f3d-11a1882211a4 (Autodesk Fusion 360 design; units mm, degrees)
Autodesk Fusion 360 part; units mm, degrees
(part 1 of 3)
sketch "Sketch1" plane through (0, 0, 0) normal (0, 1, 0) x (1, 0, 0)
  line L0 (0, 0) -> (1000, 0) construction
  line L1 (1000, 0) -> (1000, -300) construction
  line L2 (1000, -300) -> (0, -300) construction
  line L3 (0, -300) -> (0, 0) construction
  line L4 (150, -300) -> (850, -300)
  arc A0 (850, -300) -> (850, 0) centre (850, -150) ccw
  line L5 (850, 0) -> (150, 0)
  arc A1 (150, 0) -> (150, -300) centre (150, -150) ccw
  line L6 (0, -150) -> (1000, -150) construction
  arc A2 (850, -270) -> (850, -30) centre (850, -150) ccw
  line L7 (850, -30) -> (150, -30)
  arc A3 (150, -30) -> (150, -270) centre (150, -150) ccw
  line L8 (150, -270) -> (850, -270)
  dimension "d1" = 300
  dimension "d2" = 1000
  dimension "d3" = -30
  constraint horizontal L0
  constraint vertical L1
  constraint horizontal L2
  constraint vertical L3
  constraint coincident L0.start L3.end
  constraint tangent L4 A0
  constraint tangent A0 L5
  constraint parallel L4 L5
  constraint tangent L5 A1
  constraint tangent L4 A1
  constraint coincident A1 L6.start
  constraint coincident A0 L6.end
  constraint coincident A0.centre L6
  constraint coincident A1.centre L6
  constraint midpoint L1 L6.end
  constraint perpendicular L1 L6
  constraint midpoint L3 L6.start
  measures "d1" distance of L0.start L2.end
  measures "d2" distance of L0.start L0.end
extrude "Extrude1" add sketch "Sketch1" along normal blind 1000 contours L4 A0 L5 A1 | A2 L7 A3 L8 makes body 1 in component "Исходная болванка"
extrude "Extrude2" cut sketch "Sketch1" against normal blind 150 from surface at 1000 contours A2 L7 A3 L8 bodies 1 in component "Исходная болванка"
ref_plane "WorkPlane1" through (0, 0, 0) normal (0, 1, 0) x (0, 0, 1) in component "ДСП 16 — горизонталь 1"
sketch "Sketch1 (2)" plane through (0, 0, 0) normal (0, 1, 0) x (1, 0, 0) in component "ДСП 16 — горизонталь 1"
  line L0 (150, -5) -> (850, -5)
  arc A0 (850, -295) -> (850, -5) centre (850, -150) ccw
  line L1 (850, -295) -> (150, -295)
  arc A1 (150, -5) -> (150, -295) centre (150, -150) ccw
extrude "ДСП 16 — горизонталь 1" add sketch "Sketch1 (2)" along normal blind 16 separate body makes body 2 in component "ДСП 16 — горизонталь 1"
ref_plane "WorkPlane1" through (0, 245.5, 0) normal (0, 1, 0) x (0, 0, 1) in component "ДСП 16 — горизонталь 2"
sketch "Sketch1 (3)" plane through (0, 245.5, 0) normal (0, 1, 0) x (1, 0, 0) in component "ДСП 16 — горизонталь 2"
  line L0 (150, -5) -> (850, -5)
  arc A0 (850, -295) -> (850, -5) centre (850, -150) ccw
  line L1 (850, -295) -> (150, -295)
  arc A1 (150, -5) -> (150, -295) centre (150, -150) ccw
extrude "ДСП 16 — горизонталь 2" add sketch "Sketch1 (3)" along normal blind 16 separate body makes body 3 in component "ДСП 16 — горизонталь 2"
ref_plane "WorkPlane1" through (0, 491, 0) normal (0, 1, 0) x (0, 0, 1) in component "ДСП 16 — горизонталь 3"
sketch "Sketch1 (4)" plane through (0, 491, 0) normal (0, 1, 0) x (1, 0, 0) in component "ДСП 16 — горизонталь 3"
  line L0 (150, -5) -> (850, -5)
  arc A0 (850, -295) -> (850, -5) centre (850, -150) ccw
  line L1 (850, -295) -> (150, -295)
  arc A1 (150, -5) -> (150, -295) centre (150, -150) ccw
extrude "ДСП 16 — горизонталь 3" add sketch "Sketch1 (4)" along normal blind 16 separate body makes body 4 in component "ДСП 16 — горизонталь 3"
ref_plane "WorkPlane1" through (0, 736.5, 0) normal (0, 1, 0) x (0, 0, 1) in component "ДСП 16 — горизонталь 4"
sketch "Sketch1 (5)" plane through (0, 736.5, 0) normal (0, 1, 0) x (1, 0, 0) in component "ДСП 16 — горизонталь 4"
  line L0 (150, -5) -> (850, -5)
  arc A0 (850, -295) -> (850, -5) centre (850, -150) ccw
  line L1 (850, -295) -> (150, -295)
  arc A1 (150, -5) -> (150, -295) centre (150, -150) ccw
extrude "ДСП 16 — горизонталь 4" add sketch "Sketch1 (5)" along normal blind 16 separate body makes body 5 in component "ДСП 16 — горизонталь 4"
ref_plane "WorkPlane1" through (0, 982, 0) normal (0, 1, 0) x (0, 0, 1) in component "ДСП 16 — горизонталь 5"
sketch "Sketch1 (6)" plane through (0, 982, 0) normal (0, 1, 0) x (1, 0, 0) in component "ДСП 16 — горизонталь 5"
  line L0 (150, -5) -> (850, -5)
  arc A0 (850, -295) -> (850, -5) centre (850, -150) ccw
  line L1 (850, -295) -> (150, -295)
  arc A1 (150, -5) -> (150, -295) centre (150, -150) ccw
  line L2 (150, -30) -> (850, -30)
  arc A2 (850, -270) -> (850, -30) centre (850, -150) ccw
  line L3 (850, -270) -> (150, -270)
  arc A3 (150, -30) -> (150, -270) centre (150, -150) ccw
extrude "ДСП 16 — горизонталь 5" add sketch "Sketch1 (6)" along normal blind 16 separate body makes body 6 in component "ДСП 16 — горизонталь 5"
ref_plane "WorkPlane1" through (0, 0, 0) normal (0, 1, 0) x (0, 0, 1) in component "ХДФ 3 — наружная обшивка — 2 шт"
sketch "Sketch1 (7)" plane through (0, 0, 0) normal (0, 1, 0) x (1, 0, 0) in component "ХДФ 3 — наружная обшивка — 2 шт"
  line L0 (150, -2) -> (850, -2)
  arc A0 (850, -298) -> (850, -2) centre (850, -150) ccw
  line L1 (850, -298) -> (150, -298)
  arc A1 (150, -2) -> (150, -298) centre (150, -150) ccw
  line L2 (150, -5) -> (850, -5)
  arc A2 (850, -295) -> (850, -5) centre (850, -150) ccw
  line L3 (850, -295) -> (150, -295)
  arc A3 (150, -5) -> (150, -295) centre (150, -150) ccw
extrude "ХДФ 3 — наружная обшивка" add sketch "Sketch1 (7)" along normal blind 998 separate body makes body 7 in component "ХДФ 3 — наружная обшивка — 2 шт"
ref_plane "WorkPlane1" through (0, 0, 0) normal (0, 1, 0) x (0, 0, 1) in component "Полистирол 2 — наружная обшивка — 2 шт"
sketch "Sketch1 (8)" plane through (0, 0, 0) normal (0, 1, 0) x (1, 0, 0) in component "Полистирол 2 — наружная обшивка — 2 шт"
  line L0 (150, 0) -> (850, 0)
  arc A0 (850, -300) -> (850, 0) centre (850, -150) ccw
  line L1 (850, -300) -> (150, -300)
  arc A1 (150, 0) -> (150, -300) centre (150, -150) ccw
  line L2 (150, -2) -> (850, -2)
  arc A2 (850, -298) -> (850, -2) centre (850, -150) ccw
  line L3 (850, -298) -> (150, -298)
  arc A3 (150, -2) -> (150, -298) centre (150, -150) ccw
extrude "Полистирол 2 — наружная обшивка" add sketch "Sketch1 (8)" along normal blind 998 separate body makes body 8 in component "Полистирол 2 — наружная обшивка — 2 шт"
ref_plane "WorkPlane1" through (0, 998, 0) normal (0, 1, 0) x (0, 0, 1) in component "Полистирол 2 — верхнее кольцо"
sketch "Sketch1 (9)" plane through (0, 998, 0) normal (0, 1, 0) x (1, 0, 0) in component "Полистирол 2 — верхнее кольцо"
  line L0 (150, 0) -> (850, 0)
  arc A0 (850, -300) -> (850, 0) centre (850, -150) ccw
  line L1 (850, -300) -> (150, -300)
  arc A1 (150, 0) -> (150, -300) centre (150, -150) ccw
  line L2 (150, -30) -> (850, -30)
  arc A2 (850, -270) -> (850, -30) centre (850, -150) ccw
  line L3 (850, -270) -> (150, -270)
  arc A3 (150, -30) -> (150, -270) centre (150, -150) ccw
extrude "Полистирол 2 — верхнее кольцо" add sketch "Sketch1 (9)" along normal blind 2 separate body makes body 9 in component "Полистирол 2 — верхнее кольцо"
ref_plane "WorkPlane2" through (0, 0, 0) normal (0, 1, 0) x (0, 0, 1) in component "ДСП 16 — горизонталь 1"
sketch "Sketch2" plane through (0, 0, 0) normal (0, 1, 0) x (1, 0, 0) in component "ДСП 16 — горизонталь 1"
  line L0 (208, 0) -> (208, -55)
  line L1 (208, -55) -> (192, -55)
  line L2 (192, -55) -> (192, 0)
  line L3 (192, 0) -> (208, 0)
  line L4 (308, 0) -> (308, -55)
  line L5 (308, -55) -> (292, -55)
  line L6 (292, -55) -> (292, 0)
  line L7 (292, 0) -> (308, 0)
  line L8 (408, 0) -> (408, -55)
  line L9 (408, -55) -> (392, -55)
  line L10 (392, -55) -> (392, 0)
  line L11 (392, 0) -> (408, 0)
  line L12 (508, 0) -> (508, -55)
  line L13 (508, -55) -> (492, -55)
  line L14 (492, -55) -> (492, 0)
  line L15 (492, 0) -> (508, 0)
  line L16 (608, 0) -> (608, -55)
  line L17 (608, -55) -> (592, -55)
  line L18 (592, -55) -> (592, 0)
  line L19 (592, 0) -> (608, 0)
  line L20 (708, 0) -> (708, -55)
  line L21 (708, -55) -> (692, -55)
  line L22 (692, -55) -> (692, 0)
  line L23 (692, 0) -> (708, 0)
  line L24 (808, 0) -> (808, -55)
  line L25 (808, -55) -> (792, -55)
  line L26 (792, -55) -> (792, 0)
  line L27 (792, 0) -> (808, 0)
  line L28 (192, -300) -> (192, -245)
  line L29 (192, -245) -> (208, -245)
  line L30 (208, -245) -> (208, -300)
  line L31 (208, -300) -> (192, -300)
  line L32 (292, -300) -> (292, -245)
  line L33 (292, -245) -> (308, -245)
  line L34 (308, -245) -> (308, -300)
  line L35 (308, -300) -> (292, -300)
  line L36 (392, -300) -> (392, -245)
  line L37 (392, -245) -> (408, -245)
  line L38 (408, -245) -> (408, -300)
  line L39 (408, -300) -> (392, -300)
  line L40 (492, -300) -> (492, -245)
  line L41 (492, -245) -> (508, -245)
  line L42 (508, -245) -> (508, -300)
  line L43 (508, -300) -> (492, -300)
  line L44 (592, -300) -> (592, -245)
  line L45 (592, -245) -> (608, -245)
  line L46 (608, -245) -> (608, -300)
  line L47 (608, -300) -> (592, -300)
  line L48 (692, -300) -> (692, -245)
  line L49 (692, -245) -> (708, -245)
  line L50 (708, -245) -> (708, -300)
  line L51 (708, -300) -> (692, -300)
  line L52 (792, -300) -> (792, -245)
  line L53 (792, -245) -> (808, -245)
  line L54 (808, -245) -> (808, -300)
  line L55 (808, -300) -> (792, -300)
  line L56 (931.9282, -24.0962) -> (904.4282, -71.7276)
  line L57 (904.4282, -71.7276) -> (890.5718, -63.7276)
  line L58 (890.5718, -63.7276) -> (918.0718, -16.0962)
  line L59 (918.0718, -16.0962) -> (931.9282, -24.0962)
  line L60 (1000, -158) -> (945, -158)
  line L61 (945, -158) -> (945, -142)
  line L62 (945, -142) -> (1000, -142)
  line L63 (1000, -142) -> (1000, -158)
  line L64 (918.0718, -283.9038) -> (890.5718, -236.2724)
  line L65 (890.5718, -236.2724) -> (904.4282, -228.2724)
  line L66 (904.4282, -228.2724) -> (931.9282, -275.9038)
  line L67 (931.9282, -275.9038) -> (918.0718, -283.9038)
  line L68 (68.0718, -275.9038) -> (95.5718, -228.2724)
  line L69 (95.5718, -228.2724) -> (109.4282, -236.2724)
  line L70 (109.4282, -236.2724) -> (81.9282, -283.9038)
  line L71 (81.9282, -283.9038) -> (68.0718, -275.9038)
  line L72 (0, -142) -> (55, -142)
  line L73 (55, -142) -> (55, -158)
  line L74 (55, -158) -> (0, -158)
  line L75 (0, -158) -> (0, -142)
  line L76 (81.9282, -16.0962) -> (109.4282, -63.7276)
  line L77 (109.4282, -63.7276) -> (95.5718, -71.7276)
  line L78 (95.5718, -71.7276) -> (68.0718, -24.0962)
  line L79 (68.0718, -24.0962) -> (81.9282, -16.0962)
extrude "Пазы шип-паз 16 мм" cut sketch "Sketch2" along normal blind 16 contours L0 L1 L2 L3 | L8 L9 L10 L11 | L16 L17 L18 L19 | L24 L25 L26 L27 | L28 L29 L30 L31 | L36 L37 L38 L39 | L44 L45 L46 L47 | L52 L53 L54 L55 | L56 L57 L58 L59 | L60 L61 L62 L63 | L64 L65 L66 L67 | L68 L69 L70 L71 | L72 L73 L74 L75 | L76 L77 L78 L79 bodies 2 in component "ДСП 16 — горизонталь 1"
extrude "Extrude2'" [no effect] in component "ХДФ 3 — наружная обшивка — 2 шт"
extrude "Extrude2''" [no effect] in component "Полистирол 2 — наружная обшивка — 2 шт"
ref_plane "WorkPlane2" through (0, 245.5, 0) normal (0, 1, 0) x (0, 0, 1) in component "ДСП 16 — горизонталь 2"
sketch "Sketch2 (2)" plane through (0, 245.5, 0) normal (0, 1, 0) x (1, 0, 0) in component "ДСП 16 — горизонталь 2"
  line L0 (208, 0) -> (208, -55)
  line L1 (208, -55) -> (192, -55)
  line L2 (192, -55) -> (192, 0)
  line L3 (192, 0) -> (208, 0)
  line L4 (308, 0) -> (308, -55)
  line L5 (308, -55) -> (292, -55)
  line L6 (292, -55) -> (292, 0)
  line L7 (292, 0) -> (308, 0)
  line L8 (408, 0) -> (408, -55)
  line L9 (408, -55) -> (392, -55)
  line L10 (392, -55) -> (392, 0)
  line L11 (392, 0) -> (408, 0)
  line L12 (508, 0) -> (508, -55)
  line L13 (508, -55) -> (492, -55)
  line L14 (492, -55) -> (492, 0)
  line L15 (492, 0) -> (508, 0)
  line L16 (608, 0) -> (608, -55)
  line L17 (608, -55) -> (592, -55)
  line L18 (592, -55) -> (592, 0)
  line L19 (592, 0) -> (608, 0)
  line L20 (708, 0) -> (708, -55)
  line L21 (708, -55) -> (692, -55)
  line L22 (692, -55) -> (692, 0)
  line L23 (692, 0) -> (708, 0)
  line L24 (808, 0) -> (808, -55)
  line L25 (808, -55) -> (792, -55)
  line L26 (792, -55) -> (792, 0)
  line L27 (792, 0) -> (808, 0)
  line L28 (192, -300) -> (192, -245)
  line L29 (192, -245) -> (208, -245)
  line L30 (208, -245) -> (208, -300)
  line L31 (208, -300) -> (192, -300)
  line L32 (292, -300) -> (292, -245)
  line L33 (292, -245) -> (308, -245)
  line L34 (308, -245) -> (308, -300)
  line L35 (308, -300) -> (292, -300)
  line L36 (392, -300) -> (392, -245)
  line L37 (392, -245) -> (408, -245)
  line L38 (408, -245) -> (408, -300)
  line L39 (408, -300) -> (392, -300)
  line L40 (492, -300) -> (492, -245)
  line L41 (492, -245) -> (508, -245)
  line L42 (508, -245) -> (508, -300)
  line L43 (508, -300) -> (492, -300)
  line L44 (592, -300) -> (592, -245)
  line L45 (592, -245) -> (608, -245)
  line L46 (608, -245) -> (608, -300)
  line L47 (608, -300) -> (592, -300)
  line L48 (692, -300) -> (692, -245)
  line L49 (692, -245) -> (708, -245)
  line L50 (708, -245) -> (708, -300)
  line L51 (708, -300) -> (692, -300)
  line L52 (792, -300) -> (792, -245)
  line L53 (792, -245) -> (808, -245)
  line L54 (808, -245) -> (808, -300)
  line L55 (808, -300) -> (792, -300)
  line L56 (931.9282, -24.0962) -> (904.4282, -71.7276)
  line L57 (904.4282, -71.7276) -> (890.5718, -63.7276)
  line L58 (890.5718, -63.7276) -> (918.0718, -16.0962)
  line L59 (918.0718, -16.0962) -> (931.9282, -24.0962)
  line L60 (1000, -158) -> (945, -158)
  line L61 (945, -158) -> (945, -142)
  line L62 (945, -142) -> (1000, -142)
  line L63 (1000, -142) -> (1000, -158)
  line L64 (918.0718, -283.9038) -> (890.5718, -236.2724)
  line L65 (890.5718, -236.2724) -> (904.4282, -228.2724)
  line L66 (904.4282, -228.2724) -> (931.9282, -275.9038)
  line L67 (931.9282, -275.9038) -> (918.0718, -283.9038)
  line L68 (68.0718, -275.9038) -> (95.5718, -228.2724)
  line L69 (95.5718, -228.2724) -> (109.4282, -236.2724)
  line L70 (109.4282, -236.2724) -> (81.9282, -283.9038)
  line L71 (81.9282, -283.9038) -> (68.0718, -275.9038)
  line L72 (0, -142) -> (55, -142)
  line L73 (55, -142) -> (55, -158)
  line L74 (55, -158) -> (0, -158)
  line L75 (0, -158) -> (0, -142)
  line L76 (81.9282, -16.0962) -> (109.4282, -63.7276)
  line L77 (109.4282, -63.7276) -> (95.5718, -71.7276)
  line L78 (95.5718, -71.7276) -> (68.0718, -24.0962)
  line L79 (68.0718, -24.0962) -> (81.9282, -16.0962)
extrude "Пазы шип-паз 16 мм'" cut sketch "Sketch2 (2)" along normal blind 16 contours L0 L1 L2 L3 | L8 L9 L10 L11 | L16 L17 L18 L19 | L24 L25 L26 L27 | L28 L29 L30 L31 | L36 L37 L38 L39 | L44 L45 L46 L47 | L52 L53 L54 L55 | L56 L57 L58 L59 | L60 L61 L62 L63 | L64 L65 L66 L67 | L68 L69 L70 L71 | L72 L73 L74 L75 | L76 L77 L78 L79 bodies 3 in component "ДСП 16 — горизонталь 2"
extrude "Extrude3" [no effect] in component "ХДФ 3 — наружная обшивка — 2 шт"
extrude "Extrude3'" [no effect] in component "Полистирол 2 — наружная обшивка — 2 шт"
ref_plane "WorkPlane2" through (0, 491, 0) normal (0, 1, 0) x (0, 0, 1) in component "ДСП 16 — горизонталь 3"
sketch "Sketch2 (3)" plane through (0, 491, 0) normal (0, 1, 0) x (1, 0, 0) in component "ДСП 16 — горизонталь 3"
  line L0 (208, 0) -> (208, -55)
  line L1 (208, -55) -> (192, -55)
  line L2 (192, -55) -> (192, 0)
  line L3 (192, 0) -> (208, 0)
  line L4 (308, 0) -> (308, -55)
  line L5 (308, -55) -> (292, -55)
  line L6 (292, -55) -> (292, 0)
  line L7 (292, 0) -> (308, 0)
  line L8 (408, 0) -> (408, -55)
  line L9 (408, -55) -> (392, -55)
  line L10 (392, -55) -> (392, 0)
  line L11 (392, 0) -> (408, 0)
  line L12 (508, 0) -> (508, -55)
  line L13 (508, -55) -> (492, -55)
  line L14 (492, -55) -> (492, 0)
  line L15 (492, 0) -> (508, 0)
  line L16 (608, 0) -> (608, -55)
  line L17 (608, -55) -> (592, -55)
  line L18 (592, -55) -> (592, 0)
  line L19 (592, 0) -> (608, 0)
  line L20 (708, 0) -> (708, -55)
  line L21 (708, -55) -> (692, -55)
  line L22 (692, -55) -> (692, 0)
  line L23 (692, 0) -> (708, 0)
  line L24 (808, 0) -> (808, -55)
  line L25 (808, -55) -> (792, -55)
  line L26 (792, -55) -> (792, 0)
  line L27 (792, 0) -> (808, 0)
  line L28 (192, -300) -> (192, -245)
  line L29 (192, -245) -> (208, -245)
  line L30 (208, -245) -> (208, -300)
  line L31 (208, -300) -> (192, -300)
  line L32 (292, -300) -> (292, -245)
  line L33 (292, -245) -> (308, -245)
  line L34 (308, -245) -> (308, -300)
  line L35 (308, -300) -> (292, -300)
  line L36 (392, -300) -> (392, -245)
  line L37 (392, -245) -> (408, -245)
  line L38 (408, -245) -> (408, -300)
  line L39 (408, -300) -> (392, -300)
  line L40 (492, -300) -> (492, -245)
  line L41 (492, -245) -> (508, -245)
  line L42 (508, -245) -> (508, -300)
  line L43 (508, -300) -> (492, -300)
  line L44 (592, -300) -> (592, -245)
  line L45 (592, -245) -> (608, -245)
  line L46 (608, -245) -> (608, -300)
  line L47 (608, -300) -> (592, -300)
  line L48 (692, -300) -> (692, -245)
  line L49 (692, -245) -> (708, -245)
  line L50 (708, -245) -> (708, -300)
  line L51 (708, -300) -> (692, -300)
  line L52 (792, -300) -> (792, -245)
  line L53 (792, -245) -> (808, -245)
  line L54 (808, -245) -> (808, -300)
  line L55 (808, -300) -> (792, -300)
  line L56 (931.9282, -24.0962) -> (904.4282, -71.7276)
  line L57 (904.4282, -71.7276) -> (890.5718, -63.7276)
  line L58 (890.5718, -63.7276) -> (918.0718, -16.0962)
  line L59 (918.0718, -16.0962) -> (931.9282, -24.0962)
  line L60 (1000, -158) -> (945, -158)
  line L61 (945, -158) -> (945, -142)
  line L62 (945, -142) -> (1000, -142)
  line L63 (1000, -142) -> (1000, -158)
  line L64 (918.0718, -283.9038) -> (890.5718, -236.2724)
  line L65 (890.5718, -236.2724) -> (904.4282, -228.2724)
  line L66 (904.4282, -228.2724) -> (931.9282, -275.9038)
  line L67 (931.9282, -275.9038) -> (918.0718, -283.9038)
  line L68 (68.0718, -275.9038) -> (95.5718, -228.2724)
  line L69 (95.5718, -228.2724) -> (109.4282, -236.2724)
  line L70 (109.4282, -236.2724) -> (81.9282, -283.9038)
  line L71 (81.9282, -283.9038) -> (68.0718, -275.9038)
  line L72 (0, -142) -> (55, -142)
  line L73 (55, -142) -> (55, -158)
  line L74 (55, -158) -> (0, -158)
  line L75 (0, -158) -> (0, -142)
  line L76 (81.9282, -16.0962) -> (109.4282, -63.7276)
  line L77 (109.4282, -63.7276) -> (95.5718, -71.7276)
  line L78 (95.5718, -71.7276) -> (68.0718, -24.0962)
  line L79 (68.0718, -24.0962) -> (81.9282, -16.0962)
extrude "Пазы шип-паз 16 мм''" cut sketch "Sketch2 (3)" along normal blind 16 contours L0 L1 L2 L3 | L8 L9 L10 L11 | L16 L17 L18 L19 | L24 L25 L26 L27 | L28 L29 L30 L31 | L36 L37 L38 L39 | L44 L45 L46 L47 | L52 L53 L54 L55 | L56 L57 L58 L59 | L60 L61 L62 L63 | L64 L65 L66 L67 | L68 L69 L70 L71 | L72 L73 L74 L75 | L76 L77 L78 L79 bodies 4 in component "ДСП 16 — горизонталь 3"
extrude "Extrude4" [no effect] in component "ХДФ 3 — наружная обшивка — 2 шт"
extrude "Extrude4'" [no effect] in component "Полистирол 2 — наружная обшивка — 2 шт"
ref_plane "WorkPlane2" through (0, 736.5, 0) normal (0, 1, 0) x (0, 0, 1) in component "ДСП 16 — горизонталь 4"
sketch "Sketch2 (4)" plane through (0, 736.5, 0) normal (0, 1, 0) x (1, 0, 0) in component "ДСП 16 — горизонталь 4"
  line L0 (208, 0) -> (208, -55)
  line L1 (208, -55) -> (192, -55)
  line L2 (192, -55) -> (192, 0)
  line L3 (192, 0) -> (208, 0)
  line L4 (308, 0) -> (308, -55)
  line L5 (308, -55) -> (292, -55)
  line L6 (292, -55) -> (292, 0)
  line L7 (292, 0) -> (308, 0)
  line L8 (408, 0) -> (408, -55)
  line L9 (408, -55) -> (392, -55)
  line L10 (392, -55) -> (392, 0)
  line L11 (392, 0) -> (408, 0)
  line L12 (508, 0) -> (508, -55)
  line L13 (508, -55) -> (492, -55)
  line L14 (492, -55) -> (492, 0)
  line L15 (492, 0) -> (508, 0)
  line L16 (608, 0) -> (608, -55)
  line L17 (608, -55) -> (592, -55)
  line L18 (592, -55) -> (592, 0)
  line L19 (592, 0) -> (608, 0)
  line L20 (708, 0) -> (708, -55)
  line L21 (708, -55) -> (692, -55)
  line L22 (692, -55) -> (692, 0)
  line L23 (692, 0) -> (708, 0)
  line L24 (808, 0) -> (808, -55)
  line L25 (808, -55) -> (792, -55)
  line L26 (792, -55) -> (792, 0)
  line L27 (792, 0) -> (808, 0)
  line L28 (192, -300) -> (192, -245)
  line L29 (192, -245) -> (208, -245)
  line L30 (208, -245) -> (208, -300)
  line L31 (208, -300) -> (192, -300)
  line L32 (292, -300) -> (292, -245)
  line L33 (292, -245) -> (308, -245)
  line L34 (308, -245) -> (308, -300)
  line L35 (308, -300) -> (292, -300)
  line L36 (392, -300) -> (392, -245)
  line L37 (392, -245) -> (408, -245)
  line L38 (408, -245) -> (408, -300)
  line L39 (408, -300) -> (392, -300)
  line L40 (492, -300) -> (492, -245)
  line L41 (492, -245) -> (508, -245)
  line L42 (508, -245) -> (508, -300)
  line L43 (508, -300) -> (492, -300)
  line L44 (592, -300) -> (592, -245)
  line L45 (592, -245) -> (608, -245)
  line L46 (608, -245) -> (608, -300)
  line L47 (608, -300) -> (592, -300)
  line L48 (692, -300) -> (692, -245)
  line L49 (692, -245) -> (708, -245)
  line L50 (708, -245) -> (708, -300)
  line L51 (708, -300) -> (692, -300)
  line L52 (792, -300) -> (792, -245)
  line L53 (792, -245) -> (808, -245)
  line L54 (808, -245) -> (808, -300)
  line L55 (808, -300) -> (792, -300)
  line L56 (931.9282, -24.0962) -> (904.4282, -71.7276)
  line L57 (904.4282, -71.7276) -> (890.5718, -63.7276)
  line L58 (890.5718, -63.7276) -> (918.0718, -16.0962)
  line L59 (918.0718, -16.0962) -> (931.9282, -24.0962)
  line L60 (1000, -158) -> (945, -158)
  line L61 (945, -158) -> (945, -142)
  line L62 (945, -142) -> (1000, -142)
  line L63 (1000, -142) -> (1000, -158)
  line L64 (918.0718, -283.9038) -> (890.5718, -236.2724)
  line L65 (890.5718, -236.2724) -> (904.4282, -228.2724)
  line L66 (904.4282, -228.2724) -> (931.9282, -275.9038)
  line L67 (931.9282, -275.9038) -> (918.0718, -283.9038)
  line L68 (68.0718, -275.9038) -> (95.5718, -228.2724)
  line L69 (95.5718, -228.2724) -> (109.4282, -236.2724)
  line L70 (109.4282, -236.2724) -> (81.9282, -283.9038)
  line L71 (81.9282, -283.9038) -> (68.0718, -275.9038)
  line L72 (0, -142) -> (55, -142)
  line L73 (55, -142) -> (55, -158)
  line L74 (55, -158) -> (0, -158)
  line L75 (0, -158) -> (0, -142)
  line L76 (81.9282, -16.0962) -> (109.4282, -63.7276)
  line L77 (109.4282, -63.7276) -> (95.5718, -71.7276)
  line L78 (95.5718, -71.7276) -> (68.0718, -24.0962)
  line L79 (68.0718, -24.0962) -> (81.9282, -16.0962)
extrude "Пазы шип-паз 16 мм'''" cut sketch "Sketch2 (4)" along normal blind 16 contours L0 L1 L2 L3 | L8 L9 L10 L11 | L16 L17 L18 L19 | L24 L25 L26 L27 | L28 L29 L30 L31 | L36 L37 L38 L39 | L44 L45 L46 L47 | L52 L53 L54 L55 | L56 L57 L58 L59 | L60 L61 L62 L63 | L64 L65 L66 L67 | L68 L69 L70 L71 | L72 L73 L74 L75 | L76 L77 L78 L79 bodies 5 in component "ДСП 16 — горизонталь 4"
extrude "Extrude5" [no effect] in component "ХДФ 3 — наружная обшивка — 2 шт"
extrude "Extrude5'" [no effect] in component "Полистирол 2 — наружная обшивка — 2 шт"
ref_plane "WorkPlane2" through (0, 982, 0) normal (0, 1, 0) x (0, 0, 1) in component "ДСП 16 — горизонталь 5"
sketch "Sketch2 (5)" plane through (0, 982, 0) normal (0, 1, 0) x (1, 0, 0) in component "ДСП 16 — горизонталь 5"
  line L0 (208, 0) -> (208, -17.5)
  line L1 (208, -17.5) -> (192, -17.5)
  line L2 (192, -17.5) -> (192, 0)
  line L3 (192, 0) -> (208, 0)
  line L4 (308, 0) -> (308, -17.5)
  line L5 (308, -17.5) -> (292, -17.5)
  line L6 (292, -17.5) -> (292, 0)
  line L7 (292, 0) -> (308, 0)
  line L8 (408, 0) -> (408, -17.5)
  line L9 (408, -17.5) -> (392, -17.5)
  line L10 (392, -17.5) -> (392, 0)
  line L11 (392, 0) -> (408, 0)
  line L12 (508, 0) -> (508, -17.5)
  line L13 (508, -17.5) -> (492, -17.5)
  line L14 (492, -17.5) -> (492, 0)
  line L15 (492, 0) -> (508, 0)
  line L16 (608, 0) -> (608, -17.5)
  line L17 (608, -17.5) -> (592, -17.5)
  line L18 (592, -17.5) -> (592, 0)
  line L19 (592, 0) -> (608, 0)
  line L20 (708, 0) -> (708, -17.5)
  line L21 (708, -17.5) -> (692, -17.5)
  line L22 (692, -17.5) -> (692, 0)
  line L23 (692, 0) -> (708, 0)
  line L24 (808, 0) -> (808, -17.5)
  line L25 (808, -17.5) -> (792, -17.5)
  line L26 (792, -17.5) -> (792, 0)
  line L27 (792, 0) -> (808, 0)
  line L28 (192, -300) -> (192, -282.5)
  line L29 (192, -282.5) -> (208, -282.5)
  line L30 (208, -282.5) -> (208, -300)
  line L31 (208, -300) -> (192, -300)
  line L32 (292, -300) -> (292, -282.5)
  line L33 (292, -282.5) -> (308, -282.5)
  line L34 (308, -282.5) -> (308, -300)
  line L35 (308, -300) -> (292, -300)
  line L36 (392, -300) -> (392, -282.5)
  line L37 (392, -282.5) -> (408, -282.5)
  line L38 (408, -282.5) -> (408, -300)
  line L39 (408, -300) -> (392, -300)
  line L40 (492, -300) -> (492, -282.5)
  line L41 (492, -282.5) -> (508, -282.5)
  line L42 (508, -282.5) -> (508, -300)
  line L43 (508, -300) -> (492, -300)
  line L44 (592, -300) -> (592, -282.5)
  line L45 (592, -282.5) -> (608, -282.5)
  line L46 (608, -282.5) -> (608, -300)
  line L47 (608, -300) -> (592, -300)
  line L48 (692, -300) -> (692, -282.5)
  line L49 (692, -282.5) -> (708, -282.5)
  line L50 (708, -282.5) -> (708, -300)
  line L51 (708, -300) -> (692, -300)
  line L52 (792, -300) -> (792, -282.5)
  line L53 (792, -282.5) -> (808, -282.5)
  line L54 (808, -282.5) -> (808, -300)
  line L55 (808, -300) -> (792, -300)
  line L56 (931.9282, -24.0962) -> (923.1782, -39.2516)
  line L57 (923.1782, -39.2516) -> (909.3218, -31.2516)
  line L58 (909.3218, -31.2516) -> (918.0718, -16.0962)
  line L59 (918.0718, -16.0962) -> (931.9282, -24.0962)
  line L60 (1000, -158) -> (982.5, -158)
  line L61 (982.5, -158) -> (982.5, -142)
  line L62 (982.5, -142) -> (1000, -142)
  line L63 (1000, -142) -> (1000, -158)
  line L64 (918.0718, -283.9038) -> (909.3218, -268.7484)
  line L65 (909.3218, -268.7484) -> (923.1782, -260.7484)
  line L66 (923.1782, -260.7484) -> (931.9282, -275.9038)
  line L67 (931.9282, -275.9038) -> (918.0718, -283.9038)
  line L68 (68.0718, -275.9038) -> (76.8218, -260.7484)
  line L69 (76.8218, -260.7484) -> (90.6782, -268.7484)
  line L70 (90.6782, -268.7484) -> (81.9282, -283.9038)
  line L71 (81.9282, -283.9038) -> (68.0718, -275.9038)
  line L72 (0, -142) -> (17.5, -142)
  line L73 (17.5, -142) -> (17.5, -158)
  line L74 (17.5, -158) -> (0, -158)
  line L75 (0, -158) -> (0, -142)
  line L76 (81.9282, -16.0962) -> (90.6782, -31.2516)
  line L77 (90.6782, -31.2516) -> (76.8218, -39.2516)
  line L78 (76.8218, -39.2516) -> (68.0718, -24.0962)
  line L79 (68.0718, -24.0962) -> (81.9282, -16.0962)
extrude "Пазы шип-паз 16 мм''''" [suppressed] in component "ДСП 16 — горизонталь 5"
extrude "Extrude6" [no effect] in component "ХДФ 3 — наружная обшивка — 2 шт"
extrude "Extrude6'" [no effect] in component "Полистирол 2 — наружная обшивка — 2 шт"
ref_plane "WorkPlane1" through (0, 0, -8) normal (0, 0, 1) x (1, 0, 0) in component "Ламель ДСП 16 — 01"
sketch "Sketch1 (10)" plane through (0, 0, -8) normal (0, 0, 1) x (1, 0, 0) in component "Ламель ДСП 16 — 01"
  line L0 (0, 0) -> (50, 0)
  line L1 (50, 0) -> (50, 16)
  line L2 (50, 16) -> (100, 16)
  line L3 (100, 16) -> (100, 245.5)
  line L4 (100, 245.5) -> (50, 245.5)
  line L5 (50, 245.5) -> (50, 261.5)
  line L6 (50, 261.5) -> (100, 261.5)
  line L7 (100, 261.5) -> (100, 491)
  line L8 (100, 491) -> (50, 491)
  line L9 (50, 491) -> (50, 507)
  line L10 (50, 507) -> (100, 507)
  line L11 (100, 507) -> (100, 736.5)
  line L12 (100, 736.5) -> (50, 736.5)
  line L13 (50, 736.5) -> (50, 752.5)
  line L14 (50, 752.5) -> (100, 752.5)
  line L15 (100, 752.5) -> (100, 982)
  line L16 (100, 982) -> (12.5, 982)
  line L17 (12.5, 982) -> (12.5, 998)
  line L18 (12.5, 998) -> (0, 998)
  line L19 (0, 998) -> (0, 0)
extrude "Ламель 100 мм с пазами" add sketch "Sketch1 (10)" along normal blind 16 separate body makes body 10 in component "Ламель ДСП 16 — 01"
ref_plane "WorkPlane1" through (0, 0, -8) normal (0, 0, 1) x (1, 0, 0) in component "Ламель ДСП 16 — 02"
sketch "Sketch1 (11)" plane through (0, 0, -8) normal (0, 0, 1) x (1, 0, 0) in component "Ламель ДСП 16 — 02"
  line L0 (0, 0) -> (50, 0)
  line L1 (50, 0) -> (50, 16)
  line L2 (50, 16) -> (100, 16)
  line L3 (100, 16) -> (100, 245.5)
  line L4 (100, 245.5) -> (50, 245.5)
  line L5 (50, 245.5) -> (50, 261.5)
  line L6 (50, 261.5) -> (100, 261.5)
  line L7 (100, 261.5) -> (100, 491)
  line L8 (100, 491) -> (50, 491)
  line L9 (50, 491) -> (50, 507)
  line L10 (50, 507) -> (100, 507)
  line L11 (100, 507) -> (100, 736.5)
  line L12 (100, 736.5) -> (50, 736.5)
  line L13 (50, 736.5) -> (50, 752.5)
  line L14 (50, 752.5) -> (100, 752.5)
  line L15 (100, 752.5) -> (100, 982)
  line L16 (100, 982) -> (12.5, 982)
  line L17 (12.5, 982) -> (12.5, 998)
  line L18 (12.5, 998) -> (0, 998)
  line L19 (0, 998) -> (0, 0)
extrude "Ламель 100 мм с пазами'" add sketch "Sketch1 (11)" along normal blind 16 separate body makes body 11 in component "Ламель ДСП 16 — 02"
ref_plane "WorkPlane1" through (0, 0, -8) normal (0, 0, 1) x (1, 0, 0) in component "Ламель ДСП 16 — 03"
sketch "Sketch1 (12)" plane through (0, 0, -8) normal (0, 0, 1) x (1, 0, 0) in component "Ламель ДСП 16 — 03"
  line L0 (0, 0) -> (50, 0)
  line L1 (50, 0) -> (50, 16)
  line L2 (50, 16) -> (100, 16)
  line L3 (100, 16) -> (100, 245.5)
  line L4 (100, 245.5) -> (50, 245.5)
  line L5 (50, 245.5) -> (50, 261.5)
  line L6 (50, 261.5) -> (100, 261.5)
  line L7 (100, 261.5) -> (100, 491)
  line L8 (100, 491) -> (50, 491)
  line L9 (50, 491) -> (50, 507)
  line L10 (50, 507) -> (100, 507)
  line L11 (100, 507) -> (100, 736.5)
  line L12 (100, 736.5) -> (50, 736.5)
  line L13 (50, 736.5) -> (50, 752.5)
  line L14 (50, 752.5) -> (100, 752.5)
  line L15 (100, 752.5) -> (100, 982)
  line L16 (100, 982) -> (12.5, 982)
  line L17 (12.5, 982) -> (12.5, 998)
  line L18 (12.5, 998) -> (0, 998)
  line L19 (0, 998) -> (0, 0)
extrude "Ламель 100 мм с пазами''" add sketch "Sketch1 (12)" along normal blind 16 separate body makes body 12 in component "Ламель ДСП 16 — 03"
ref_plane "WorkPlane1" through (0, 0, -8) normal (0, 0, 1) x (1, 0, 0) in component "Ламель ДСП 16 — 04"
sketch "Sketch1 (13)" plane through (0, 0, -8) normal (0, 0, 1) x (1, 0, 0) in component "Ламель ДСП 16 — 04"
  line L0 (0, 0) -> (50, 0)
  line L1 (50, 0) -> (50, 16)
  line L2 (50, 16) -> (100, 16)
  line L3 (100, 16) -> (100, 245.5)
  line L4 (100, 245.5) -> (50, 245.5)
  line L5 (50, 245.5) -> (50, 261.5)
  line L6 (50, 261.5) -> (100, 261.5)
  line L7 (100, 261.5) -> (100, 491)
  line L8 (100, 491) -> (50, 491)
  line L9 (50, 491) -> (50, 507)
  line L10 (50, 507) -> (100, 507)
  line L11 (100, 507) -> (100, 736.5)
  line L12 (100, 736.5) -> (50, 736.5)
  line L13 (50, 736.5) -> (50, 752.5)
  line L14 (50, 752.5) -> (100, 752.5)
  line L15 (100, 752.5) -> (100, 982)
  line L16 (100, 982) -> (12.5, 982)
  line L17 (12.5, 982) -> (12.5, 998)
  line L18 (12.5, 998) -> (0, 998)
  line L19 (0, 998) -> (0, 0)
extrude "Ламель 100 мм с пазами'''" add sketch "Sketch1 (13)" along normal blind 16 separate body makes body 13 in component "Ламель ДСП 16 — 04"
ref_plane "WorkPlane1" through (0, 0, -8) normal (0, 0, 1) x (1, 0, 0) in component "Ламель ДСП 16 — 05"
sketch "Sketch1 (14)" plane through (0, 0, -8) normal (0, 0, 1) x (1, 0, 0) in component "Ламель ДСП 16 — 05"
  line L0 (0, 0) -> (50, 0)
  line L1 (50, 0) -> (50, 16)
  line L2 (50, 16) -> (100, 16)
  line L3 (100, 16) -> (100, 245.5)
  line L4 (100, 245.5) -> (50, 245.5)
  line L5 (50, 245.5) -> (50, 261.5)
  line L6 (50, 261.5) -> (100, 261.5)
  line L7 (100, 261.5) -> (100, 491)
  line L8 (100, 491) -> (50, 491)
  line L9 (50, 491) -> (50, 507)
  line L10 (50, 507) -> (100, 507)
  line L11 (100, 507) -> (100, 736.5)
  line L12 (100, 736.5) -> (50, 736.5)
  line L13 (50, 736.5) -> (50, 752.5)
  line L14 (50, 752.5) -> (100, 752.5)
  line L15 (100, 752.5) -> (100, 982)
  line L16 (100, 982) -> (12.5, 982)
  line L17 (12.5, 982) -> (12.5, 998)
  line L18 (12.5, 998) -> (0, 998)
  line L19 (0, 998) -> (0, 0)
extrude "Ламель 100 мм с пазами''''" add sketch "Sketch1 (14)" along normal blind 16 separate body makes body 14 in component "Ламель ДСП 16 — 05"
ref_plane "WorkPlane1" through (0, 0, -8) normal (0, 0, 1) x (1, 0, 0) in component "Ламель ДСП 16 — 06"
sketch "Sketch1 (15)" plane through (0, 0, -8) normal (0, 0, 1) x (1, 0, 0) in component "Ламель ДСП 16 — 06"
  line L0 (0, 0) -> (50, 0)
  line L1 (50, 0) -> (50, 16)
  line L2 (50, 16) -> (100, 16)
  line L3 (100, 16) -> (100, 245.5)
  line L4 (100, 245.5) -> (50, 245.5)
  line L5 (50, 245.5) -> (50, 261.5)
  line L6 (50, 261.5) -> (100, 261.5)
  line L7 (100, 261.5) -> (100, 491)
  line L8 (100, 491) -> (50, 491)
  line L9 (50, 491) -> (50, 507)
  line L10 (50, 507) -> (100, 507)
  line L11 (100, 507) -> (100, 736.5)
  line L12 (100, 736.5) -> (50, 736.5)
  line L13 (50, 736.5) -> (50, 752.5)
  line L14 (50, 752.5) -> (100, 752.5)
  line L15 (100, 752.5) -> (100, 982)
  line L16 (100, 982) -> (12.5, 982)
  line L17 (12.5, 982) -> (12.5, 998)
  line L18 (12.5, 998) -> (0, 998)
  line L19 (0, 998) -> (0, 0)
extrude "Ламель 100 мм с пазами'''''" add sketch "Sketch1 (15)" along normal blind 16 separate body makes body 15 in component "Ламель ДСП 16 — 06"
ref_plane "WorkPlane1" through (0, 0, -8) normal (0, 0, 1) x (1, 0, 0) in component "Ламель ДСП 16 — 07"
sketch "Sketch1 (16)" plane through (0, 0, -8) normal (0, 0, 1) x (1, 0, 0) in component "Ламель ДСП 16 — 07"
  line L0 (0, 0) -> (50, 0)
  line L1 (50, 0) -> (50, 16)
  line L2 (50, 16) -> (100, 16)
  line L3 (100, 16) -> (100, 245.5)
  line L4 (100, 245.5) -> (50, 245.5)
  line L5 (50, 245.5) -> (50, 261.5)
  line L6 (50, 261.5) -> (100, 261.5)
  line L7 (100, 261.5) -> (100, 491)
  line L8 (100, 491) -> (50, 491)
  line L9 (50, 491) -> (50, 507)
  line L10 (50, 507) -> (100, 507)
  line L11 (100, 507) -> (100, 736.5)
  line L12 (100, 736.5) -> (50, 736.5)
  line L13 (50, 736.5) -> (50, 752.5)
  line L14 (50, 752.5) -> (100, 752.5)
  line L15 (100, 752.5) -> (100, 982)
  line L16 (100, 982) -> (12.5, 982)
  line L17 (12.5, 982) -> (12.5, 998)
  line L18 (12.5, 998) -> (0, 998)
  line L19 (0, 998) -> (0, 0)
extrude "Ламель 100 мм с пазами''''''" add sketch "Sketch1 (16)" along normal blind 16 separate body makes body 16 in component "Ламель ДСП 16 — 07"
ref_plane "WorkPlane1" through (0, 0, -8) normal (0, 0, 1) x (1, 0, 0) in component "Ламель ДСП 16 — 08"
sketch "Sketch1 (17)" plane through (0, 0, -8) normal (0, 0, 1) x (1, 0, 0) in component "Ламель ДСП 16 — 08"
  line L0 (0, 0) -> (50, 0)
  line L1 (50, 0) -> (50, 16)
  line L2 (50, 16) -> (100, 16)
  line L3 (100, 16) -> (100, 245.5)
  line L4 (100, 245.5) -> (50, 245.5)
  line L5 (50, 245.5) -> (50, 261.5)
  line L6 (50, 261.5) -> (100, 261.5)
  line L7 (100, 261.5) -> (100, 491)
  line L8 (100, 491) -> (50, 491)
  line L9 (50, 491) -> (50, 507)
  line L10 (50, 507) -> (100, 507)
  line L11 (100, 507) -> (100, 736.5)
  line L12 (100, 736.5) -> (50, 736.5)
  line L13 (50, 736.5) -> (50, 752.5)
  line L14 (50, 752.5) -> (100, 752.5)
  line L15 (100, 752.5) -> (100, 982)
  line L16 (100, 982) -> (12.5, 982)
  line L17 (12.5, 982) -> (12.5, 998)
  line L18 (12.5, 998) -> (0, 998)
  line L19 (0, 998) -> (0, 0)
extrude "Ламель 100 мм с пазами'''''''" add sketch "Sketch1 (17)" along normal blind 16 separate body makes body 17 in component "Ламель ДСП 16 — 08"
ref_plane "WorkPlane1" through (0, 0, -8) normal (0, 0, 1) x (1, 0, 0) in component "Ламель ДСП 16 — 09"
sketch "Sketch1 (18)" plane through (0, 0, -8) normal (0, 0, 1) x (1, 0, 0) in component "Ламель ДСП 16 — 09"
  line L0 (0, 0) -> (50, 0)
  line L1 (50, 0) -> (50, 16)
  line L2 (50, 16) -> (100, 16)
  line L3 (100, 16) -> (100, 245.5)
  line L4 (100, 245.5) -> (50, 245.5)
  line L5 (50, 245.5) -> (50, 261.5)
  line L6 (50, 261.5) -> (100, 261.5)
  line L7 (100, 261.5) -> (100, 491)
  line L8 (100, 491) -> (50, 491)
  line L9 (50, 491) -> (50, 507)
  line L10 (50, 507) -> (100, 507)
  line L11 (100, 507) -> (100, 736.5)
  line L12 (100, 736.5) -> (50, 736.5)
  line L13 (50, 736.5) -> (50, 752.5)
  line L14 (50, 752.5) -> (100, 752.5)
  line L15 (100, 752.5) -> (100, 982)
  line L16 (100, 982) -> (12.5, 982)
  line L17 (12.5, 982) -> (12.5, 998)
  line L18 (12.5, 998) -> (0, 998)
  line L19 (0, 998) -> (0, 0)
extrude "Ламель 100 мм с пазами''''''''" add sketch "Sketch1 (18)" along normal blind 16 separate body makes body 18 in component "Ламель ДСП 16 — 09"
ref_plane "WorkPlane1" through (0, 0, -8) normal (0, 0, 1) x (1, 0, 0) in component "Ламель ДСП 16 — 10"
sketch "Sketch1 (19)" plane through (0, 0, -8) normal (0, 0, 1) x (1, 0, 0) in component "Ламель ДСП 16 — 10"
  line L0 (0, 0) -> (50, 0)
  line L1 (50, 0) -> (50, 16)
  line L2 (50, 16) -> (100, 16)
  line L3 (100, 16) -> (100, 245.5)
  line L4 (100, 245.5) -> (50, 245.5)
  line L5 (50, 245.5) -> (50, 261.5)
  line L6 (50, 261.5) -> (100, 261.5)
  line L7 (100, 261.5) -> (100, 491)
  line L8 (100, 491) -> (50, 491)
  line L9 (50, 491) -> (50, 507)
  line L10 (50, 507) -> (100, 507)
  line L11 (100, 507) -> (100, 736.5)
  line L12 (100, 736.5) -> (50, 736.5)
  line L13 (50, 736.5) -> (50, 752.5)
  line L14 (50, 752.5) -> (100, 752.5)
  line L15 (100, 752.5) -> (100, 982)
  line L16 (100, 982) -> (12.5, 982)
  line L17 (12.5, 982) -> (12.5, 998)
  line L18 (12.5, 998) -> (0, 998)
  line L19 (0, 998) -> (0, 0)
extrude "Ламель 100 мм с пазами'''''''''" add sketch "Sketch1 (19)" along normal blind 16 separate body makes body 19 in component "Ламель ДСП 16 — 10"
ref_plane "WorkPlane1" through (0, 0, -8) normal (0, 0, 1) x (1, 0, 0) in component "Ламель ДСП 16 — 11"
sketch "Sketch1 (20)" plane through (0, 0, -8) normal (0, 0, 1) x (1, 0, 0) in component "Ламель ДСП 16 — 11"
  line L0 (0, 0) -> (50, 0)
  line L1 (50, 0) -> (50, 16)
  line L2 (50, 16) -> (100, 16)
  line L3 (100, 16) -> (100, 245.5)
  line L4 (100, 245.5) -> (50, 245.5)
  line L5 (50, 245.5) -> (50, 261.5)
  line L6 (50, 261.5) -> (100, 261.5)
  line L7 (100, 261.5) -> (100, 491)
  line L8 (100, 491) -> (50, 491)
  line L9 (50, 491) -> (50, 507)
  line L10 (50, 507) -> (100, 507)
  line L11 (100, 507) -> (100, 736.5)
  line L12 (100, 736.5) -> (50, 736.5)
  line L13 (50, 736.5) -> (50, 752.5)
  line L14 (50, 752.5) -> (100, 752.5)
  line L15 (100, 752.5) -> (100, 982)
  line L16 (100, 982) -> (12.5, 982)
  line L17 (12.5, 982) -> (12.5, 998)
  line L18 (12.5, 998) -> (0, 998)
  line L19 (0, 998) -> (0, 0)
extrude "Ламель 100 мм с пазами''''''''''" add sketch "Sketch1 (20)" along normal blind 16 separate body makes body 20 in component "Ламель ДСП 16 — 11"
ref_plane "WorkPlane1" through (0, 0, -8) normal (0, 0, 1) x (1, 0, 0) in component "Ламель ДСП 16 — 12"
sketch "Sketch1 (21)" plane through (0, 0, -8) normal (0, 0, 1) x (1, 0, 0) in component "Ламель ДСП 16 — 12"
  line L0 (0, 0) -> (50, 0)
  line L1 (50, 0) -> (50, 16)
  line L2 (50, 16) -> (100, 16)
  line L3 (100, 16) -> (100, 245.5)
  line L4 (100, 245.5) -> (50, 245.5)
  line L5 (50, 245.5) -> (50, 261.5)
  line L6 (50, 261.5) -> (100, 261.5)
  line L7 (100, 261.5) -> (100, 491)
  line L8 (100, 491) -> (50, 491)
  line L9 (50, 491) -> (50, 507)
  line L10 (50, 507) -> (100, 507)
  line L11 (100, 507) -> (100, 736.5)
  line L12 (100, 736.5) -> (50, 736.5)
  line L13 (50, 736.5) -> (50, 752.5)
  line L14 (50, 752.5) -> (100, 752.5)
  line L15 (100, 752.5) -> (100, 982)
  line L16 (100, 982) -> (12.5, 982)
  line L17 (12.5, 982) -> (12.5, 998)
  line L18 (12.5, 998) -> (0, 998)
  line L19 (0, 998) -> (0, 0)
extrude "Ламель 100 мм с пазами'''''''''''" add sketch "Sketch1 (21)" along normal blind 16 separate body makes body 21 in component "Ламель ДСП 16 — 12"
ref_plane "WorkPlane1" through (0, 0, -8) normal (0, 0, 1) x (1, 0, 0) in component "Ламель ДСП 16 — 13"
sketch "Sketch1 (22)" plane through (0, 0, -8) normal (0, 0, 1) x (1, 0, 0) in component "Ламель ДСП 16 — 13"
  line L0 (0, 0) -> (50, 0)
  line L1 (50, 0) -> (50, 16)
  line L2 (50, 16) -> (100, 16)
  line L3 (100, 16) -> (100, 245.5)
  line L4 (100, 245.5) -> (50, 245.5)
  line L5 (50, 245.5) -> (50, 261.5)
  line L6 (50, 261.5) -> (100, 261.5)
  line L7 (100, 261.5) -> (100, 491)
  line L8 (100, 491) -> (50, 491)
  line L9 (50, 491) -> (50, 507)
  line L10 (50, 507) -> (100, 507)
  line L11 (100, 507) -> (100, 736.5)
  line L12 (100, 736.5) -> (50, 736.5)
  line L13 (50, 736.5) -> (50, 752.5)
  line L14 (50, 752.5) -> (100, 752.5)
  line L15 (100, 752.5) -> (100, 982)
  line L16 (100, 982) -> (12.5, 982)
  line L17 (12.5, 982) -> (12.5, 998)
  line L18 (12.5, 998) -> (0, 998)
  line L19 (0, 998) -> (0, 0)
extrude "Ламель 100 мм с пазами''''''''''''" add sketch "Sketch1 (22)" along normal blind 16 separate body makes body 22 in component "Ламель ДСП 16 — 13"
ref_plane "WorkPlane1" through (0, 0, -8) normal (0, 0, 1) x (1, 0, 0) in component "Ламель ДСП 16 — 14"
sketch "Sketch1 (23)" plane through (0, 0, -8) normal (0, 0, 1) x (1, 0, 0) in component "Ламель ДСП 16 — 14"
  line L0 (0, 0) -> (50, 0)
  line L1 (50, 0) -> (50, 16)
  line L2 (50, 16) -> (100, 16)
  line L3 (100, 16) -> (100, 245.5)
  line L4 (100, 245.5) -> (50, 245.5)
  line L5 (50, 245.5) -> (50, 261.5)
  line L6 (50, 261.5) -> (100, 261.5)
  line L7 (100, 261.5) -> (100, 491)
  line L8 (100, 491) -> (50, 491)
  line L9 (50, 491) -> (50, 507)
  line L10 (50, 507) -> (100, 507)
  line L11 (100, 507) -> (100, 736.5)
  line L12 (100, 736.5) -> (50, 736.5)
  line L13 (50, 736.5) -> (50, 752.5)
  line L14 (50, 752.5) -> (100, 752.5)
  line L15 (100, 752.5) -> (100, 982)
  line L16 (100, 982) -> (12.5, 982)
  line L17 (12.5, 982) -> (12.5, 998)
  line L18 (12.5, 998) -> (0, 998)
  line L19 (0, 998) -> (0, 0)
extrude "Ламель 100 мм с пазами'''''''''''''" add sketch "Sketch1 (23)" along normal blind 16 separate body makes body 23 in component "Ламель ДСП 16 — 14"
ref_plane "WorkPlane1" through (0, 0, -8) normal (0, 0, 1) x (1, 0, 0) in component "Ламель ДСП 16 — 15"
sketch "Sketch1 (24)" plane through (0, 0, -8) normal (0, 0, 1) x (1, 0, 0) in component "Ламель ДСП 16 — 15"
  line L0 (0, 0) -> (50, 0)
  line L1 (50, 0) -> (50, 16)
  line L2 (50, 16) -> (100, 16)
  line L3 (100, 16) -> (100, 245.5)
  line L4 (100, 245.5) -> (50, 245.5)
  line L5 (50, 245.5) -> (50, 261.5)
  line L6 (50, 261.5) -> (100, 261.5)
  line L7 (100, 261.5) -> (100, 491)
  line L8 (100, 491) -> (50, 491)
  line L9 (50, 491) -> (50, 507)
  line L10 (50, 507) -> (100, 507)
  line L11 (100, 507) -> (100, 736.5)
  line L12 (100, 736.5) -> (50, 736.5)
  line L13 (50, 736.5) -> (50, 752.5)
  line L14 (50, 752.5) -> (100, 752.5)
  line L15 (100, 752.5) -> (100, 982)
  line L16 (100, 982) -> (12.5, 982)
  line L17 (12.5, 982) -> (12.5, 998)
  line L18 (12.5, 998) -> (0, 998)
  line L19 (0, 998) -> (0, 0)
extrude "Ламель 100 мм с пазами''''''''''''''" add sketch "Sketch1 (24)" along normal blind 16 separate body makes body 24 in component "Ламель ДСП 16 — 15"
ref_plane "WorkPlane2" through (0, 0, 0) normal (0, 1, 0) x (0, 0, 1) in component "Ламель ДСП 16 — 15"
sketch "Sketch2 (6)" plane through (0, 0, 0) normal (0, 1, 0) x (1, 0, 0) in component "Ламель ДСП 16 — 15"
  line L0 (-10, 8) -> (0.2209, 8)
  arc A0 (0.2209, 8) -> (0.2209, -8) centre (145, 0) ccw
  line L1 (0.2209, -8) -> (-10, -8)
  line L2 (-10, -8) -> (-10, 8)
extrude "Подгонка по радиусу наружной облицовки" [suppressed] in component "ХДФ 3 — наружная обшивка — 2 шт"
extrude "Extrude7" [no effect] in component "Полистирол 2 — наружная обшивка — 2 шт"
extrude "Extrude2'''" cut sketch "Sketch2 (6)" along normal blind 998 bodies 24 in component "Ламель ДСП 16 — 15"
ref_plane "WorkPlane1" through (0, 0, -8) normal (0, 0, 1) x (1, 0, 0) in component "Ламель ДСП 16 — 16"
sketch "Sketch1 (25)" plane through (0, 0, -8) normal (0, 0, 1) x (1, 0, 0) in component "Ламель ДСП 16 — 16"
  line L0 (0, 0) -> (50, 0)
  line L1 (50, 0) -> (50, 16)
  line L2 (50, 16) -> (100, 16)
  line L3 (100, 16) -> (100, 245.5)
  line L4 (100, 245.5) -> (50, 245.5)
  line L5 (50, 245.5) -> (50, 261.5)
  line L6 (50, 261.5) -> (100, 261.5)
  line L7 (100, 261.5) -> (100, 491)
  line L8 (100, 491) -> (50, 491)
  line L9 (50, 491) -> (50, 507)
  line L10 (50, 507) -> (100, 507)
  line L11 (100, 507) -> (100, 736.5)
  line L12 (100, 736.5) -> (50, 736.5)
  line L13 (50, 736.5) -> (50, 752.5)
  line L14 (50, 752.5) -> (100, 752.5)
  line L15 (100, 752.5) -> (100, 982)
  line L16 (100, 982) -> (12.5, 982)
  line L17 (12.5, 982) -> (12.5, 998)
  line L18 (12.5, 998) -> (0, 998)
  line L19 (0, 998) -> (0, 0)
extrude "Ламель 100 мм с пазами'''''''''''''''" add sketch "Sketch1 (25)" along normal blind 16 separate body makes body 25 in component "Ламель ДСП 16 — 16"
ref_plane "WorkPlane2" through (0, 0, 0) normal (0, 1, 0) x (0, 0, 1) in component "Ламель ДСП 16 — 16"
sketch "Sketch2 (7)" plane through (0, 0, 0) normal (0, 1, 0) x (1, 0, 0) in component "Ламель ДСП 16 — 16"
  line L0 (-10, 8) -> (0.2209, 8)
  arc A0 (0.2209, 8) -> (0.2209, -8) centre (145, 0) ccw
  line L1 (0.2209, -8) -> (-10, -8)
  line L2 (-10, -8) -> (-10, 8)
extrude "Подгонка по радиусу наружной облицовки (1)" [suppressed] in component "ХДФ 3 — наружная обшивка — 2 шт"
extrude "Extrude8" [no effect] in component "Полистирол 2 — наружная обшивка — 2 шт"
extrude "Extrude2''''" cut sketch "Sketch2 (7)" along normal blind 998 bodies 25 in component "Ламель ДСП 16 — 16"
ref_plane "WorkPlane1" through (0, 0, -8) normal (0, 0, 1) x (1, 0, 0) in component "Ламель ДСП 16 — 17"
sketch "Sketch1 (26)" plane through (0, 0, -8) normal (0, 0, 1) x (1, 0, 0) in component "Ламель ДСП 16 — 17"
  line L0 (0, 0) -> (50, 0)
  line L1 (50, 0) -> (50, 16)
  line L2 (50, 16) -> (100, 16)
  line L3 (100, 16) -> (100, 245.5)
  line L4 (100, 245.5) -> (50, 245.5)
  line L5 (50, 245.5) -> (50, 261.5)
  line L6 (50, 261.5) -> (100, 261.5)
  line L7 (100, 261.5) -> (100, 491)
  line L8 (100, 491) -> (50, 491)
  line L9 (50, 491) -> (50, 507)
  line L10 (50, 507) -> (100, 507)
  line L11 (100, 507) -> (100, 736.5)
  line L12 (100, 736.5) -> (50, 736.5)
  line L13 (50, 736.5) -> (50, 752.5)
  line L14 (50, 752.5) -> (100, 752.5)
  line L15 (100, 752.5) -> (100, 982)
  line L16 (100, 982) -> (12.5, 982)
  line L17 (12.5, 982) -> (12.5, 998)
  line L18 (12.5, 998) -> (0, 998)
  line L19 (0, 998) -> (0, 0)
extrude "Ламель 100 мм с пазами''''''''''''''''" add sketch "Sketch1 (26)" along normal blind 16 separate body makes body 26 in component "Ламель ДСП 16 — 17"
ref_plane "WorkPlane2" through (0, 0, 0) normal (0, 1, 0) x (0, 0, 1) in component "Ламель ДСП 16 — 17"
sketch "Sketch2 (8)" plane through (0, 0, 0) normal (0, 1, 0) x (1, 0, 0) in component "Ламель ДСП 16 — 17"
  line L0 (-10, 8) -> (0.2209, 8)
  arc A0 (0.2209, 8) -> (0.2209, -8) centre (145, 0) ccw
  line L1 (0.2209, -8) -> (-10, -8)
  line L2 (-10, -8) -> (-10, 8)
extrude "Подгонка по радиусу наружной облицовки (2)" [suppressed] in component "ХДФ 3 — наружная обшивка — 2 шт"
extrude "Extrude9" [no effect] in component "Полистирол 2 — наружная обшивка — 2 шт"
extrude "Extrude2'''''" cut sketch "Sketch2 (8)" along normal blind 998 bodies 26 in component "Ламель ДСП 16 — 17"
ref_plane "WorkPlane1" through (0, 0, -8) normal (0, 0, 1) x (1, 0, 0) in component "Ламель ДСП 16 — 18"
sketch "Sketch1 (27)" plane through (0, 0, -8) normal (0, 0, 1) x (1, 0, 0) in component "Ламель ДСП 16 — 18"
  line L0 (0, 0) -> (50, 0)
  line L1 (50, 0) -> (50, 16)
  line L2 (50, 16) -> (100, 16)
  line L3 (100, 16) -> (100, 245.5)
  line L4 (100, 245.5) -> (50, 245.5)
  line L5 (50, 245.5) -> (50, 261.5)
  line L6 (50, 261.5) -> (100, 261.5)
  line L7 (100, 261.5) -> (100, 491)
  line L8 (100, 491) -> (50, 491)
  line L9 (50, 491) -> (50, 507)
  line L10 (50, 507) -> (100, 507)
  line L11 (100, 507) -> (100, 736.5)
  line L12 (100, 736.5) -> (50, 736.5)
  line L13 (50, 736.5) -> (50, 752.5)
  line L14 (50, 752.5) -> (100, 752.5)
  line L15 (100, 752.5) -> (100, 982)
  line L16 (100, 982) -> (12.5, 982)
  line L17 (12.5, 982) -> (12.5, 998)
  line L18 (12.5, 998) -> (0, 998)
  line L19 (0, 998) -> (0, 0)
extrude "Ламель 100 мм с пазами'''''''''''''''''" add sketch "Sketch1 (27)" along normal blind 16 separate body makes body 27 in component "Ламель ДСП 16 — 18"
ref_plane "WorkPlane2" through (0, 0, 0) normal (0, 1, 0) x (0, 0, 1) in component "Ламель ДСП 16 — 18"
sketch "Sketch2 (9)" plane through (0, 0, 0) normal (0, 1, 0) x (1, 0, 0) in component "Ламель ДСП 16 — 18"
  line L0 (-10, 8) -> (0.2209, 8)
  arc A0 (0.2209, 8) -> (0.2209, -8) centre (145, 0) ccw
  line L1 (0.2209, -8) -> (-10, -8)
  line L2 (-10, -8) -> (-10, 8)
extrude "Подгонка по радиусу наружной облицовки (3)" [suppressed] in component "ХДФ 3 — наружная обшивка — 2 шт"
extrude "Extrude10" [no effect] in component "Полистирол 2 — наружная обшивка — 2 шт"
extrude "Extrude2''''''" cut sketch "Sketch2 (9)" along normal blind 998 bodies 27 in component "Ламель ДСП 16 — 18"
ref_plane "WorkPlane1" through (0, 0, -8) normal (0, 0, 1) x (1, 0, 0) in component "Ламель ДСП 16 — 19"
sketch "Sketch1 (28)" plane through (0, 0, -8) normal (0, 0, 1) x (1, 0, 0) in component "Ламель ДСП 16 — 19"
  line L0 (0, 0) -> (50, 0)
  line L1 (50, 0) -> (50, 16)
  line L2 (50, 16) -> (100, 16)
  line L3 (100, 16) -> (100, 245.5)
  line L4 (100, 245.5) -> (50, 245.5)
  line L5 (50, 245.5) -> (50, 261.5)
  line L6 (50, 261.5) -> (100, 261.5)
  line L7 (100, 261.5) -> (100, 491)
  line L8 (100, 491) -> (50, 491)
  line L9 (50, 491) -> (50, 507)
  line L10 (50, 507) -> (100, 507)
  line L11 (100, 507) -> (100, 736.5)
  line L12 (100, 736.5) -> (50, 736.5)
  line L13 (50, 736.5) -> (50, 752.5)
  line L14 (50, 752.5) -> (100, 752.5)
  line L15 (100, 752.5) -> (100, 982)
  line L16 (100, 982) -> (12.5, 982)
  line L17 (12.5, 982) -> (12.5, 998)
  line L18 (12.5, 998) -> (0, 998)
  line L19 (0, 998) -> (0, 0)